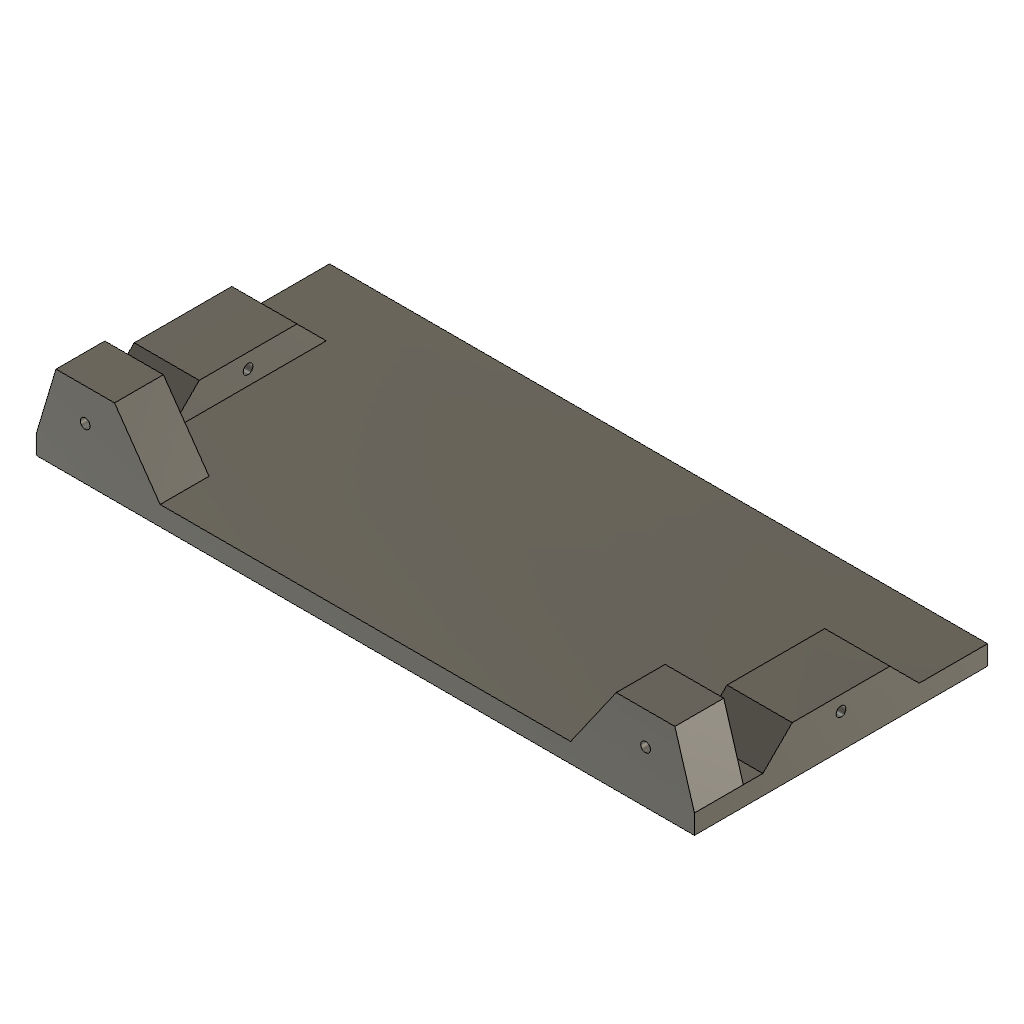
Clock Bottom (Autodesk Fusion 360 design; units mm, degrees)
Autodesk Fusion 360 part; units mm, degrees
sketch "Sketch1" plane through (0, 0, 0) normal (0, 0, 1) x (1, 0, 0)
  line L0 (101, 45) -> (-101, 45)
  line L1 (-101, 45) -> (-101, -45)
  line L2 (-101, -45) -> (101, -45)
  line L3 (101, -45) -> (101, 45)
  line L4 (101, 45) -> (-101, -45) construction
  line L5 (-101, 45) -> (101, -45) construction
  dimension "d1" = 202
  dimension "d2" = 90
  constraint horizontal L0
  constraint perpendicular L0 L1
  constraint parallel L0 L2
  constraint parallel L1 L3
  constraint coincident L4 origin
  constraint coincident L5 origin
  measures "d1" distance of L1.end L2.end
  measures "d2" distance of L0.end L1.end
extrude "Extrude1" add sketch "Sketch1" along normal blind 6
sketch "Sketch2" plane through (101, 0, 0) normal (1, 0, 0) x (0, 1, 0)
  line L0 (-45, 0) -> (45, 0)
  line L1 (45, 0) -> (45, 6)
  line L2 (45, 6) -> (-45, 6)
  line L3 (-45, 6) -> (-45, 0)
  line L4 (-45, 0) -> (45, 0)
  line L5 (45, 0) -> (45, 15)
  line L6 (45, 15) -> (-45, 15)
  line L7 (-45, 15) -> (-45, 0)
  line L8 (0, 6) -> (0, 15)
  circle A0 centre (0, 10.5) radius 1.5
  line L9 (15, 15) -> (-15, 15)
  line L10 (-15, 15) -> (-15, 6)
  line L11 (-15, 6) -> (15, 6)
  line L12 (15, 6) -> (15, 15)
  line L13 (15, 15) -> (-15, 6) construction
  line L14 (-15, 15) -> (15, 6) construction
  line L15 (15, 15) -> (24, 6)
  line L16 (-15, 15) -> (-24.842, 5.158)
  point P0 (0, 10.5)
  dimension "d5" = 90
  dimension "d6" = 15
  dimension "d7" = 3
  dimension "d8" = 90
  constraint horizontal L4
  constraint vertical L5
  constraint horizontal L6
  constraint vertical L7
  constraint coincident L0.start L3.end
  constraint midpoint L2 L8.start
  constraint midpoint L6 L8.end
  constraint midpoint L8 P0
  constraint horizontal L9
  constraint perpendicular L9 L10
  constraint parallel L9 L11
  constraint parallel L10 L12
  constraint coincident L13 P0
  constraint coincident L14 P0
  constraint coincident L6 L9.start
  constraint coincident P0 A0.centre
  constraint coincident L2 L15.end
  measures "d5" distance of L0.start L0.end
  measures "d6" distance of L0.start L6.end
  measures "d7" diameter of A0
  measures "d8" angle of L15 L16
extrude "Extrude2" add sketch "Sketch2" against normal blind 20 contours L2 L10 L16 | L2 L12 L15 | L2 L6 L8 A0 L9 L10 L11 | L2 L6 L8 A0 L9 L11 L12
sketch "Sketch3" plane through (-101, 0, 0) normal (-1, 0, 0) x (0, -1, 0)
  line L0 (-45, 0) -> (45, 0)
  line L1 (45, 0) -> (45, 6)
  line L2 (45, 6) -> (-45, 6)
  line L3 (-45, 6) -> (-45, 0)
  line L4 (24, 6) -> (15, 15)
  line L5 (15, 15) -> (-15, 15)
  line L6 (-15, 15) -> (-24, 6)
  circle A0 centre (0, 10.5) radius 1.5
  circle A1 centre (0, 10.5) radius 1.5
  point P0 (24, 6)
  point P1 (15, 15)
  point P2 (-15, 15)
  point P3 (-24, 6)
  dimension "d11" = 3
  constraint coincident P0 L4.start
  constraint coincident P1 L4.end
  constraint coincident P2 L5.end
  constraint coincident P3 L6.end
  constraint concentric A0 A1
  measures "d11" diameter of A0
extrude "Extrude3" add sketch "Sketch3" against normal blind 20 contours L2 L4 L5 L6
sketch "Sketch4" plane through (0, -45, 0) normal (0, -1, 0) x (1, 0, 0)
  line L0 (-101, 0) -> (101, 0)
  line L1 (101, 0) -> (101, 6)
  line L2 (101, 6) -> (-101, 6)
  line L3 (-101, 6) -> (-101, 0)
  line L4 (-101, 6) -> (-86, 6)
  line L5 (-86, 6) -> (-86, 16)
  line L6 (-86, 16) -> (-101, 16)
  line L7 (-101, 16) -> (-101, 6)
  line L8 (101, 6) -> (86, 6)
  line L9 (86, 6) -> (86, 16)
  line L10 (86, 16) -> (101, 16)
  line L11 (101, 16) -> (101, 6)
  circle A0 centre (-86, 16) radius 1.5
  circle A1 centre (86, 16) radius 1.5
  line L12 (-77, 6) -> (-95, 6)
  line L13 (-95, 6) -> (-95, 26)
  line L14 (-95, 26) -> (-77, 26)
  line L15 (-77, 26) -> (-77, 6)
  line L16 (-77, 6) -> (-95, 26) construction
  line L17 (-95, 6) -> (-77, 26) construction
  line L18 (95, 6) -> (77, 6)
  line L19 (77, 6) -> (77, 26)
  line L20 (77, 26) -> (95, 26)
  line L21 (95, 26) -> (95, 6)
  line L22 (95, 6) -> (77, 26) construction
  line L23 (77, 6) -> (95, 26) construction
  line L24 (95, 26) -> (101, 6)
  line L25 (-95, 26) -> (-101, 6)
  line L26 (-77, 26) -> (-59.9849, 1.6999)
  line L27 (-77, 26) -> (-47.3351, 26) construction
  line L28 (77, 26) -> (60.6516, 2.652)
  line L29 (77, 26) -> (105.5026, 26) construction
  point P0 (-86, 16)
  point P1 (86, 16)
  dimension "d18" = 15
  dimension "d19" = 10
  dimension "d20" = 15
  dimension "d21" = 10
  dimension "d22" = 3
  dimension "d23" = 3
  dimension "d24" = 18
  dimension "d25" = 55
  dimension "d26" = 125
  constraint horizontal L4
  constraint vertical L5
  constraint horizontal L6
  constraint vertical L7
  constraint coincident L2.end L3.start
  constraint horizontal L8
  constraint vertical L9
  constraint horizontal L10
  constraint vertical L11
  constraint coincident L1.end L2.start
  constraint coincident P0 L5.end
  constraint coincident P1 L9.end
  constraint horizontal L12
  constraint perpendicular L12 L13
  constraint parallel L12 L14
  constraint parallel L13 L15
  constraint coincident L16 P0
  constraint coincident L17 P0
  constraint coincident L2 L12.start
  constraint horizontal L18
  constraint perpendicular L18 L19
  constraint parallel L18 L20
  constraint parallel L19 L21
  constraint coincident L22 P1
  constraint coincident L23 P1
  constraint horizontal L27
  constraint horizontal L29
  measures "d18" distance of L2.end L4.end
  measures "d19" distance of L2.end L6.end
  measures "d20" distance of L1.end L8.end
  measures "d21" distance of L1.end L10.end
  measures "d22" diameter of A0
  measures "d23" diameter of A1
  measures "d24" distance of L19.end L20.end
  measures "d25" angle of L26 L27
  measures "d26" angle of L28 L29
extrude "Extrude4" add sketch "Sketch4" against normal blind 15 contours L2 L4 L6 L13 L25 | L2 L8 L10 L21 L24 | L2 L4 L5 L6 A0 L12 L13 | L6 L13 L25 | L2 L8 L9 L10 A1 L18 L21 | L10 L21 L24 | L2 L5 L6 A0 L12 L13 L14 L15 | L2 L9 L10 A1 L18 L19 L20 L21 | L2 L15 L26 | L2 L19 L28
